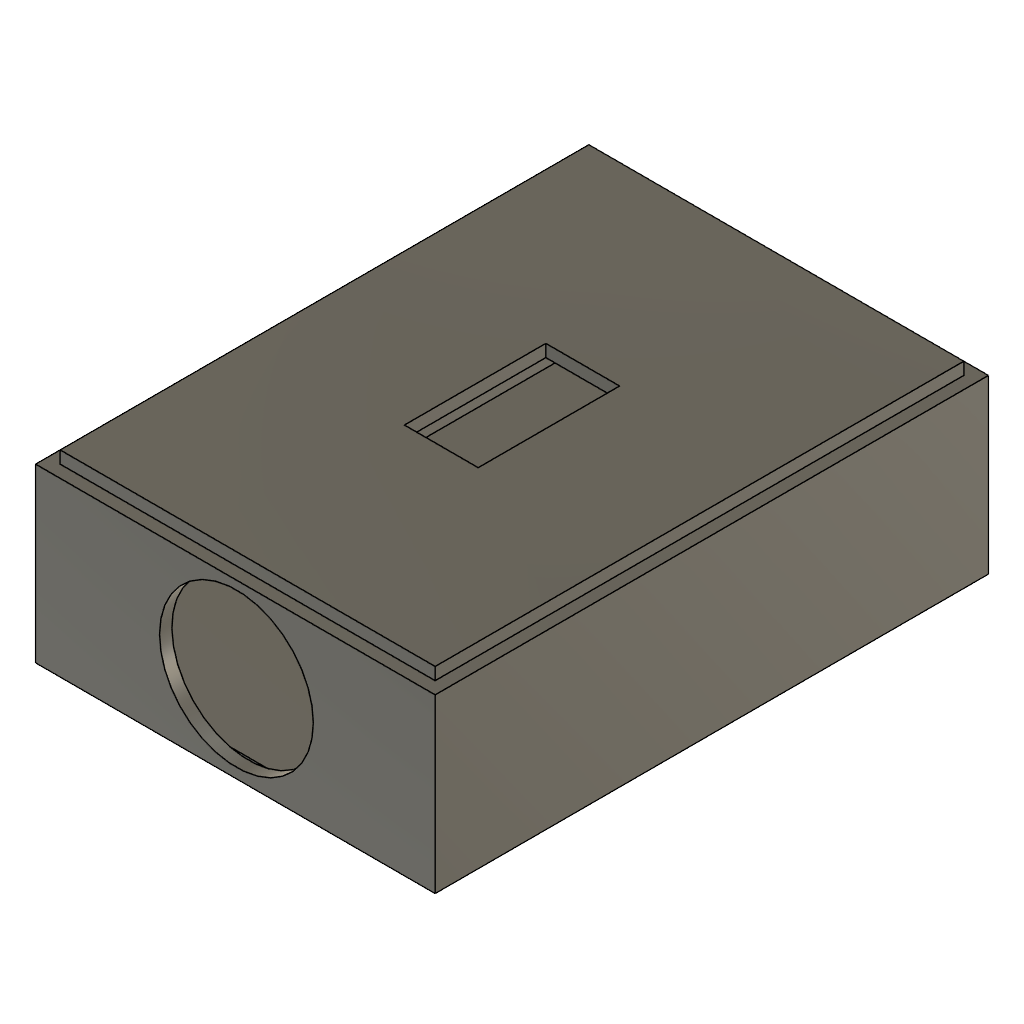
Encapsulado_Agua_Clara_v01 (Autodesk Fusion 360 design; units mm, degrees)
part number: 2026-10-19-19-35-13-771
Autodesk Fusion 360 part; units mm, degrees
sketch "Boceto1" plane through (0, 0, 0) normal (0, 0, 1) x (1, 0, 0)
  line L0 (-32.5, 45) -> (32.5, 45)
  line L1 (32.5, 45) -> (32.5, -45)
  line L2 (32.5, -45) -> (-32.5, -45)
  line L3 (-32.5, -45) -> (-32.5, 45)
  line L4 (-32.5, 45) -> (32.5, -45) construction
  line L5 (32.5, 45) -> (-32.5, -45) construction
  dimension "d1" = 65
  dimension "d2" = 90
  constraint horizontal L0
  constraint perpendicular L0 L1
  constraint parallel L0 L2
  constraint parallel L1 L3
  constraint coincident L4 origin
  constraint coincident L5 origin
  measures "d1" distance of L1.end L2.end
  measures "d2" distance of L0.end L1.end
extrude "Extruir1" add sketch "Boceto1" along normal blind 28 makes body 1
shell "Vaciado1" thickness 2 removed faces 1 at (-10.8333, 15, 28) on bodies 1
sketch "Boceto2" plane through (0, 0, 28) normal (0, 0, 1) x (-1, 0, 0)
  line L0 (30.5, 43) -> (30.5, -43)
  line L1 (30.5, -43) -> (-30.5, -43)
  line L2 (-30.5, -43) -> (-30.5, 43)
  line L3 (-30.5, 43) -> (30.5, 43)
  line L4 (32.5, 45) -> (-32.5, 45)
  line L5 (-32.5, 45) -> (-32.5, -45)
  line L6 (-32.5, -45) -> (32.5, -45)
  line L7 (32.5, -45) -> (32.5, 45)
  line L8 (-32.5, -45) -> (32.5, -45)
  line L9 (32.5, -45) -> (32.5, 45)
  line L10 (-32.5, 45) -> (-32.5, -45)
  line L11 (32.5, 45) -> (-32.5, 45)
extrude "Extruir2" add sketch "Boceto2" along normal blind 2 separate body contours L0 L1 L2 L3 makes body 2
sketch "Boceto3" plane through (0, 0, 30) normal (0, 0, 1) x (-1, 0, 0)
  line L0 (-30.5, 43) -> (-30.5, -43)
  line L1 (-30.5, -43) -> (30.5, -43)
  line L2 (30.5, -43) -> (30.5, 43)
  line L3 (30.5, 43) -> (-30.5, 43)
  line L4 (-6, -11.5) -> (6, -11.5)
  line L5 (6, -11.5) -> (6, 11.5)
  line L6 (6, 11.5) -> (-6, 11.5)
  line L7 (-6, 11.5) -> (-6, -11.5)
  line L8 (-6, -11.5) -> (6, 11.5) construction
  line L9 (6, -11.5) -> (-6, 11.5) construction
  dimension "d8" = 12
  dimension "d9" = 23
  constraint horizontal L4
  constraint perpendicular L4 L5
  constraint parallel L4 L6
  constraint parallel L5 L7
  constraint coincident L8 origin
  constraint coincident L9 origin
  measures "d8" distance of L5.end L6.end
  measures "d9" distance of L4.end L5.end
extrude "Extruir3" cut sketch "Boceto3" against normal blind 2 contours L4 L5 L6 L7 bodies 2
sketch "Boceto4" plane through (0, -45, 0) normal (0, -1, 0) x (1, 0, 0)
  line L0 (-32.5, 0) -> (32.5, 0)
  line L1 (32.5, 0) -> (32.5, 28)
  line L2 (32.5, 28) -> (-32.5, 28)
  line L3 (-32.5, 28) -> (-32.5, 0)
  circle A0 centre (0.1834, 14.1225) radius 12.5
  dimension "d12" = 25
  measures "d12" diameter of A0
extrude "Extruir4" cut sketch "Boceto4" against normal blind 2 contours A0 bodies 1
named bodies: "Caja_inferior", "Tapa_superior"
